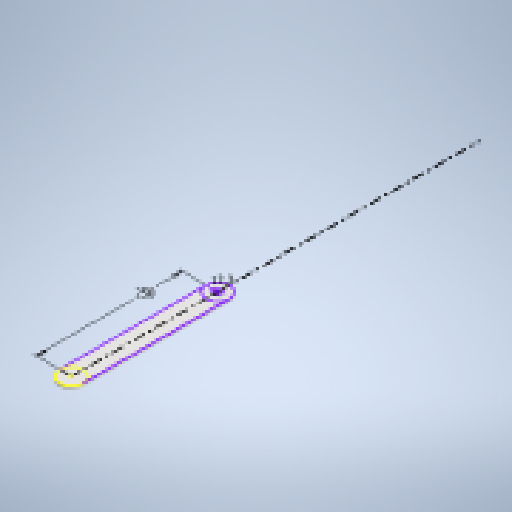
# Autodesk Inventor part: плечо r2
Saved by Autodesk Inventor 2024.2 (Build 282272000, 272)
## iProperties
Created: 2026-10-20
Part Number: плечо r2
Material: Типовые
Document SubType Name: Modeling
Designer: katya_notebook
Density: 1 g/cm^3
Appearance: По умолчанию
Author: katya_notebook
Autodesk Inventor part; units mm, degrees
ref_plane "YZ Plane" through (0, 0, 0) normal (1, 0, 0) x (0, 1, 0)
ref_plane "XZ Plane" through (0, 0, 0) normal (0, 1, 0) x (-1, 0, 0)
ref_plane "XY Plane" through (0, 0, 0) normal (0, 0, 1) x (1, 0, 0)
sketch "Эскиз1" plane through (0, 0, 0) normal (0, 1, 0) x (-1, 0, 0)
  circle A0 centre (0, 0) radius 20
  dimension "d0" = 40
  constraints: 1 centre point, 1 coincident
  measures "d0" diameter of A0
extrude "Выдавливание1" add sketch "Эскиз1" along normal blind 6
sketch "Эскиз2" plane through (0, 6, 0) normal (0, 1, 0) x (1, 0, 0)
  line L0 (0, 0) -> (0, 697.1594)
  circle A0 centre (0, 250) radius 20
  line L1 (0, 0) -> (-20, 0)
  line L2 (0, 250) -> (-20, 250)
  line L3 (-20, 0) -> (-20, 250)
  line L4 (20, 0) -> (20, 250)
  circle A1 centre (0, 250) radius 6.15
  circle A2 centre (0, 0) radius 20 projected
  dimension "d3" = 250
  dimension "d8" = 12.3
  constraints: 10 end point, 3 point on circle, 2 centre point, 2 coincident, 2 vertical, 1 horizontal, 1 parallel, 1 point on line, 1 tangent
  measures "d3" distance of L1.end L3.end
  measures "d8" diameter of A1
extrude "Выдавливание2" add sketch "Эскиз2" against normal blind 6 contours A2 L3 A0 L0 | L0 A0 L4 A2 | A0 L2 A1 L0 | L0 A1 A0 | A0 L0 A1 L2 | A1 L2 L0 | L0 A1 | A1 L0 L2
extrude "Выдавливание5" cut sketch "Эскиз2" against normal blind 30 contours A1 L2 L0 | L0 A1 | A1 L0 L2
extrude "Выдавливание6" [suppressed]
sketch "Эскиз3" plane through (0, 0, 0) normal (0, -1, 0) x (1, 0, 0)
  circle A0 centre (0, -250) radius 9.5
  circle A1 centre (0, 0) radius 12.0296
  circle A2 centre (0, -240.5) radius 1.5
  circle A3 centre (-8.2272, -245.25) radius 1.5
  circle A4 centre (-8.2272, -254.75) radius 1.5
  circle A5 centre (0, -259.5) radius 1.5
  circle A6 centre (8.2272, -254.75) radius 1.5
  circle A7 centre (8.2272, -245.25) radius 1.5
  dimension "d16" = 19
  dimension "d15" = 250
  dimension "d17" = 3
  dimension "d20" = 360
  constraints: 7 centre point, 1 coincident, 1 vertical alignment, 15 other
  measures "d15" distance of point (0, -250) point (0, 0)
  measures "d17" diameter of A2
extrude "Выдавливание7" cut sketch "Эскиз3" against normal blind 6 contours A7 A0 | A0 A7 | A6 A0 | A0 A6 | A2 A0 | A0 A2 | A5 A0 | A0 A5 | A3 A0 | A0 A3 | A4 A0 | A0 A4
chamfer "Фаска1" distance 1 angle 45 6 edges at (-9.7272, 6, -254.75) (-9.7272, 6, -245.25) (-1.5, 6, -259.5) (6.7272, 6, -254.75) (6.7272, 6, -245.25) (-1.5, 6, -240.5)
